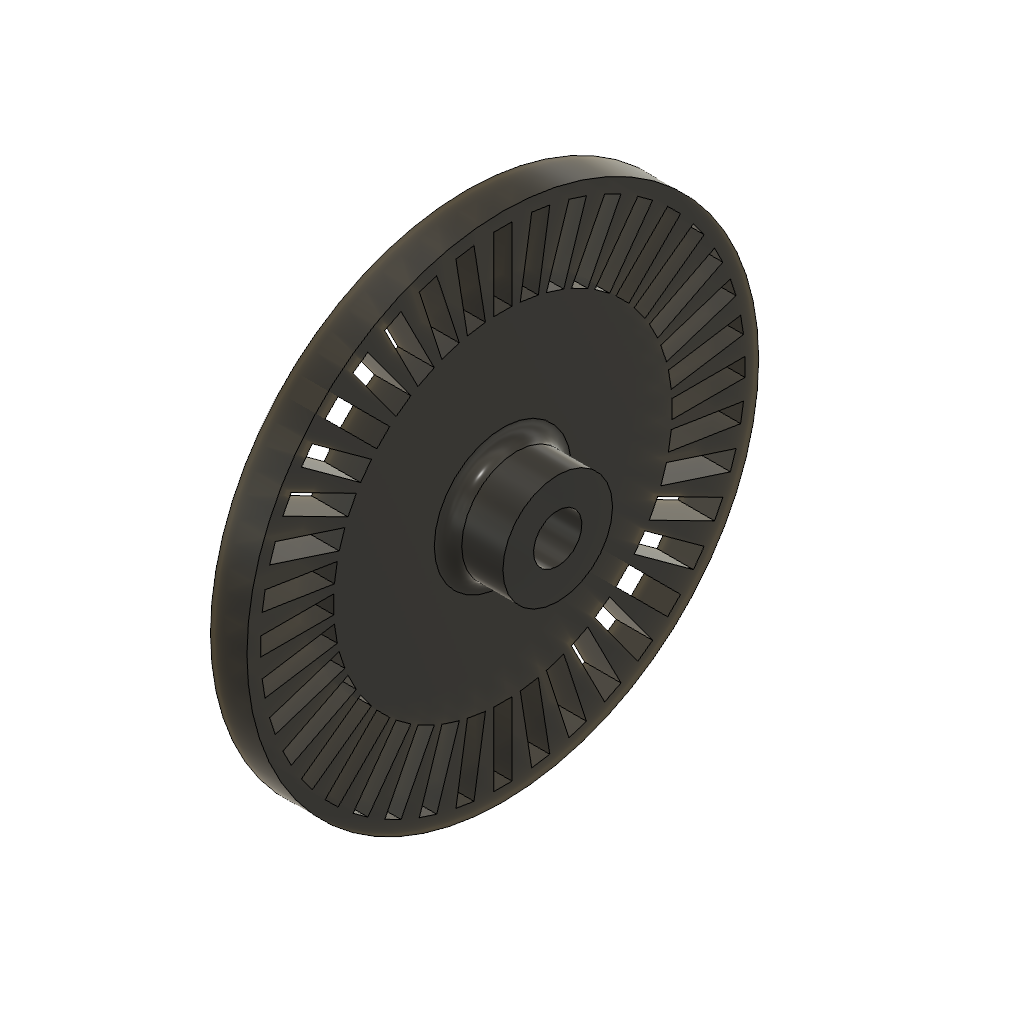
rueda_dentada_encoder (Autodesk Fusion 360 design; units mm, degrees)
Autodesk Fusion 360 part; units mm, degrees
sketch "Boceto1" plane through (0, 0, 0) normal (1, 0, 0) x (0, 0, -1)
  circle A0 centre (0, 0) radius 28
  line L0 (1.644, -2.0784) -> (1.644, 2.0784)
  line L1 (1.644, 2.0784) -> (-1.5819, -2) construction
  line L2 (-1.5819, 2) -> (1.644, -2.0784) construction
  arc A1 (1.644, 2.0784) -> (1.644, -2.0784) centre (0, 0) ccw
  circle A2 centre (0, 0) radius 26.5 construction
  line L3 (0, 0) -> (0, 29.9293) construction
  line L4 (0, 26.5) -> (-4.3464, 26.5) construction
  line L5 (0, 26.5) -> (0, 18.5)
  line L6 (0, 18.5) -> (-1, 18.5)
  line L7 (-1, 18.5) -> (-1, 26.5)
  line L8 (-1, 26.5) -> (0, 26.5)
  line L9 (1, 26.5) -> (0, 26.5)
  line L10 (1, 18.5) -> (1, 26.5)
  line L11 (0, 18.5) -> (1, 18.5)
  line L12 (-3.8817, 18.1158) -> (-5.1332, 26.0173)
  line L13 (-5.1332, 26.0173) -> (-4.1455, 26.1737)
  line L14 (-3.1578, 26.3302) -> (-4.1455, 26.1737)
  line L15 (-1.9063, 18.4287) -> (-3.1578, 26.3302)
  line L16 (-2.894, 18.2722) -> (-1.9063, 18.4287)
  line L17 (-2.894, 18.2722) -> (-3.8817, 18.1158)
  line L18 (-6.6679, 17.2855) -> (-9.14, 24.894)
  line L19 (-9.14, 24.894) -> (-8.189, 25.203)
  line L20 (-7.2379, 25.512) -> (-8.189, 25.203)
  line L21 (-4.7658, 17.9036) -> (-7.2379, 25.512)
  line L22 (-5.7168, 17.5945) -> (-4.7658, 17.9036)
  line L23 (-5.7168, 17.5945) -> (-6.6679, 17.2855)
  line L24 (-9.2898, 16.0296) -> (-12.9218, 23.1577)
  line L25 (-12.9218, 23.1577) -> (-12.0307, 23.6117)
  line L26 (-11.1397, 24.0657) -> (-12.0307, 23.6117)
  line L27 (-7.5078, 16.9376) -> (-11.1397, 24.0657)
  line L28 (-8.3988, 16.4836) -> (-7.5078, 16.9376)
  line L29 (-8.3988, 16.4836) -> (-9.2898, 16.0296)
  line L30 (-11.683, 14.379) -> (-16.3853, 20.8512)
  line L31 (-16.3853, 20.8512) -> (-15.5763, 21.439)
  line L32 (-14.7673, 22.0267) -> (-15.5763, 21.439)
  line L33 (-10.065, 15.5546) -> (-14.7673, 22.0267)
  line L34 (-10.874, 14.9668) -> (-10.065, 15.5546)
  line L35 (-10.874, 14.9668) -> (-11.683, 14.379)
  line L36 (-13.7886, 12.3744) -> (-19.4454, 18.0312)
  line L37 (-19.4454, 18.0312) -> (-18.7383, 18.7383)
  line L38 (-18.0312, 19.4454) -> (-18.7383, 18.7383)
  line L39 (-12.3744, 13.7886) -> (-18.0312, 19.4454)
  line L40 (-13.0815, 13.0815) -> (-12.3744, 13.7886)
  line L41 (-13.0815, 13.0815) -> (-13.7886, 12.3744)
  line L42 (-15.5546, 10.065) -> (-22.0267, 14.7673)
  line L43 (-22.0267, 14.7673) -> (-21.439, 15.5763)
  line L44 (-20.8512, 16.3853) -> (-21.439, 15.5763)
  line L45 (-14.379, 11.683) -> (-20.8512, 16.3853)
  line L46 (-14.9668, 10.874) -> (-14.379, 11.683)
  line L47 (-14.9668, 10.874) -> (-15.5546, 10.065)
  line L48 (-16.9376, 7.5078) -> (-24.0657, 11.1397)
  line L49 (-24.0657, 11.1397) -> (-23.6117, 12.0307)
  line L50 (-23.1577, 12.9218) -> (-23.6117, 12.0307)
  line L51 (-16.0296, 9.2898) -> (-23.1577, 12.9218)
  line L52 (-16.4836, 8.3988) -> (-16.0296, 9.2898)
  line L53 (-16.4836, 8.3988) -> (-16.9376, 7.5078)
  line L54 (-17.9036, 4.7658) -> (-25.512, 7.2379)
  line L55 (-25.512, 7.2379) -> (-25.203, 8.189)
  line L56 (-24.894, 9.14) -> (-25.203, 8.189)
  line L57 (-17.2855, 6.6679) -> (-24.894, 9.14)
  line L58 (-17.5945, 5.7168) -> (-17.2855, 6.6679)
  line L59 (-17.5945, 5.7168) -> (-17.9036, 4.7658)
  line L60 (-18.4287, 1.9063) -> (-26.3302, 3.1578)
  line L61 (-26.3302, 3.1578) -> (-26.1737, 4.1455)
  line L62 (-26.0173, 5.1332) -> (-26.1737, 4.1455)
  line L63 (-18.1158, 3.8817) -> (-26.0173, 5.1332)
  line L64 (-18.2722, 2.894) -> (-18.1158, 3.8817)
  line L65 (-18.2722, 2.894) -> (-18.4287, 1.9063)
  line L66 (-18.5, -1) -> (-26.5, -1)
  line L67 (-26.5, -1) -> (-26.5, 0)
  line L68 (-26.5, 1) -> (-26.5, 0)
  line L69 (-18.5, 1) -> (-26.5, 1)
  line L70 (-18.5, 0) -> (-18.5, 1)
  line L71 (-18.5, 0) -> (-18.5, -1)
  line L72 (-18.1158, -3.8817) -> (-26.0173, -5.1332)
  line L73 (-26.0173, -5.1332) -> (-26.1737, -4.1455)
  line L74 (-26.3302, -3.1578) -> (-26.1737, -4.1455)
  line L75 (-18.4287, -1.9063) -> (-26.3302, -3.1578)
  line L76 (-18.2722, -2.894) -> (-18.4287, -1.9063)
  line L77 (-18.2722, -2.894) -> (-18.1158, -3.8817)
  line L78 (-17.2855, -6.6679) -> (-24.894, -9.14)
  line L79 (-24.894, -9.14) -> (-25.203, -8.189)
  line L80 (-25.512, -7.2379) -> (-25.203, -8.189)
  line L81 (-17.9036, -4.7658) -> (-25.512, -7.2379)
  line L82 (-17.5945, -5.7168) -> (-17.9036, -4.7658)
  line L83 (-17.5945, -5.7168) -> (-17.2855, -6.6679)
  line L84 (-16.0296, -9.2898) -> (-23.1577, -12.9218)
  line L85 (-23.1577, -12.9218) -> (-23.6117, -12.0307)
  line L86 (-24.0657, -11.1397) -> (-23.6117, -12.0307)
  line L87 (-16.9376, -7.5078) -> (-24.0657, -11.1397)
  line L88 (-16.4836, -8.3988) -> (-16.9376, -7.5078)
  line L89 (-16.4836, -8.3988) -> (-16.0296, -9.2898)
  line L90 (-14.379, -11.683) -> (-20.8512, -16.3853)
  line L91 (-20.8512, -16.3853) -> (-21.439, -15.5763)
  line L92 (-22.0267, -14.7673) -> (-21.439, -15.5763)
  line L93 (-15.5546, -10.065) -> (-22.0267, -14.7673)
  line L94 (-14.9668, -10.874) -> (-15.5546, -10.065)
  line L95 (-14.9668, -10.874) -> (-14.379, -11.683)
  line L96 (-12.3744, -13.7886) -> (-18.0312, -19.4454)
  line L97 (-18.0312, -19.4454) -> (-18.7383, -18.7383)
  line L98 (-19.4454, -18.0312) -> (-18.7383, -18.7383)
  line L99 (-13.7886, -12.3744) -> (-19.4454, -18.0312)
  line L100 (-13.0815, -13.0815) -> (-13.7886, -12.3744)
  line L101 (-13.0815, -13.0815) -> (-12.3744, -13.7886)
  line L102 (-10.065, -15.5546) -> (-14.7673, -22.0267)
  line L103 (-14.7673, -22.0267) -> (-15.5763, -21.439)
  line L104 (-16.3853, -20.8512) -> (-15.5763, -21.439)
  line L105 (-11.683, -14.379) -> (-16.3853, -20.8512)
  line L106 (-10.874, -14.9668) -> (-11.683, -14.379)
  line L107 (-10.874, -14.9668) -> (-10.065, -15.5546)
  line L108 (-7.5078, -16.9376) -> (-11.1397, -24.0657)
  line L109 (-11.1397, -24.0657) -> (-12.0307, -23.6117)
  line L110 (-12.9218, -23.1577) -> (-12.0307, -23.6117)
  line L111 (-9.2898, -16.0296) -> (-12.9218, -23.1577)
  line L112 (-8.3988, -16.4836) -> (-9.2898, -16.0296)
  line L113 (-8.3988, -16.4836) -> (-7.5078, -16.9376)
  line L114 (-4.7658, -17.9036) -> (-7.2379, -25.512)
  line L115 (-7.2379, -25.512) -> (-8.189, -25.203)
  line L116 (-9.14, -24.894) -> (-8.189, -25.203)
  line L117 (-6.6679, -17.2855) -> (-9.14, -24.894)
  line L118 (-5.7168, -17.5945) -> (-6.6679, -17.2855)
  line L119 (-5.7168, -17.5945) -> (-4.7658, -17.9036)
  line L120 (-1.9063, -18.4287) -> (-3.1578, -26.3302)
  line L121 (-3.1578, -26.3302) -> (-4.1455, -26.1737)
  line L122 (-5.1332, -26.0173) -> (-4.1455, -26.1737)
  line L123 (-3.8817, -18.1158) -> (-5.1332, -26.0173)
  line L124 (-2.894, -18.2722) -> (-3.8817, -18.1158)
  line L125 (-2.894, -18.2722) -> (-1.9063, -18.4287)
  line L126 (1, -18.5) -> (1, -26.5)
  line L127 (1, -26.5) -> (0, -26.5)
  line L128 (-1, -26.5) -> (0, -26.5)
  line L129 (-1, -18.5) -> (-1, -26.5)
  line L130 (0, -18.5) -> (-1, -18.5)
  line L131 (0, -18.5) -> (1, -18.5)
  line L132 (3.8817, -18.1158) -> (5.1332, -26.0173)
  line L133 (5.1332, -26.0173) -> (4.1455, -26.1737)
  line L134 (3.1578, -26.3302) -> (4.1455, -26.1737)
  line L135 (1.9063, -18.4287) -> (3.1578, -26.3302)
  line L136 (2.894, -18.2722) -> (1.9063, -18.4287)
  line L137 (2.894, -18.2722) -> (3.8817, -18.1158)
  line L138 (6.6679, -17.2855) -> (9.14, -24.894)
  line L139 (9.14, -24.894) -> (8.189, -25.203)
  line L140 (7.2379, -25.512) -> (8.189, -25.203)
  line L141 (4.7658, -17.9036) -> (7.2379, -25.512)
  line L142 (5.7168, -17.5945) -> (4.7658, -17.9036)
  line L143 (5.7168, -17.5945) -> (6.6679, -17.2855)
  line L144 (9.2898, -16.0296) -> (12.9218, -23.1577)
  line L145 (12.9218, -23.1577) -> (12.0307, -23.6117)
  line L146 (11.1397, -24.0657) -> (12.0307, -23.6117)
  line L147 (7.5078, -16.9376) -> (11.1397, -24.0657)
  line L148 (8.3988, -16.4836) -> (7.5078, -16.9376)
  line L149 (8.3988, -16.4836) -> (9.2898, -16.0296)
  line L150 (11.683, -14.379) -> (16.3853, -20.8512)
  line L151 (16.3853, -20.8512) -> (15.5763, -21.439)
  line L152 (14.7673, -22.0267) -> (15.5763, -21.439)
  line L153 (10.065, -15.5546) -> (14.7673, -22.0267)
  line L154 (10.874, -14.9668) -> (10.065, -15.5546)
  line L155 (10.874, -14.9668) -> (11.683, -14.379)
  line L156 (13.7886, -12.3744) -> (19.4454, -18.0312)
  line L157 (19.4454, -18.0312) -> (18.7383, -18.7383)
  line L158 (18.0312, -19.4454) -> (18.7383, -18.7383)
  line L159 (12.3744, -13.7886) -> (18.0312, -19.4454)
  line L160 (13.0815, -13.0815) -> (12.3744, -13.7886)
  line L161 (13.0815, -13.0815) -> (13.7886, -12.3744)
  line L162 (15.5546, -10.065) -> (22.0267, -14.7673)
  line L163 (22.0267, -14.7673) -> (21.439, -15.5763)
  line L164 (20.8512, -16.3853) -> (21.439, -15.5763)
  line L165 (14.379, -11.683) -> (20.8512, -16.3853)
  line L166 (14.9668, -10.874) -> (14.379, -11.683)
  line L167 (14.9668, -10.874) -> (15.5546, -10.065)
  line L168 (16.9376, -7.5078) -> (24.0657, -11.1397)
  line L169 (24.0657, -11.1397) -> (23.6117, -12.0307)
  line L170 (23.1577, -12.9218) -> (23.6117, -12.0307)
  line L171 (16.0296, -9.2898) -> (23.1577, -12.9218)
  line L172 (16.4836, -8.3988) -> (16.0296, -9.2898)
  line L173 (16.4836, -8.3988) -> (16.9376, -7.5078)
  line L174 (17.9036, -4.7658) -> (25.512, -7.2379)
  line L175 (25.512, -7.2379) -> (25.203, -8.189)
  line L176 (24.894, -9.14) -> (25.203, -8.189)
  line L177 (17.2855, -6.6679) -> (24.894, -9.14)
  line L178 (17.5945, -5.7168) -> (17.2855, -6.6679)
  line L179 (17.5945, -5.7168) -> (17.9036, -4.7658)
  line L180 (18.4287, -1.9063) -> (26.3302, -3.1578)
  line L181 (26.3302, -3.1578) -> (26.1737, -4.1455)
  line L182 (26.0173, -5.1332) -> (26.1737, -4.1455)
  line L183 (18.1158, -3.8817) -> (26.0173, -5.1332)
  line L184 (18.2722, -2.894) -> (18.1158, -3.8817)
  line L185 (18.2722, -2.894) -> (18.4287, -1.9063)
  line L186 (18.5, 1) -> (26.5, 1)
  line L187 (26.5, 1) -> (26.5, 0)
  line L188 (26.5, -1) -> (26.5, 0)
  line L189 (18.5, -1) -> (26.5, -1)
  line L190 (18.5, 0) -> (18.5, -1)
  line L191 (18.5, 0) -> (18.5, 1)
  line L192 (18.1158, 3.8817) -> (26.0173, 5.1332)
  line L193 (26.0173, 5.1332) -> (26.1737, 4.1455)
  line L194 (26.3302, 3.1578) -> (26.1737, 4.1455)
  line L195 (18.4287, 1.9063) -> (26.3302, 3.1578)
  line L196 (18.2722, 2.894) -> (18.4287, 1.9063)
  line L197 (18.2722, 2.894) -> (18.1158, 3.8817)
  line L198 (17.2855, 6.6679) -> (24.894, 9.14)
  line L199 (24.894, 9.14) -> (25.203, 8.189)
  line L200 (25.512, 7.2379) -> (25.203, 8.189)
  line L201 (17.9036, 4.7658) -> (25.512, 7.2379)
  line L202 (17.5945, 5.7168) -> (17.9036, 4.7658)
  line L203 (17.5945, 5.7168) -> (17.2855, 6.6679)
  line L204 (16.0296, 9.2898) -> (23.1577, 12.9218)
  line L205 (23.1577, 12.9218) -> (23.6117, 12.0307)
  line L206 (24.0657, 11.1397) -> (23.6117, 12.0307)
  line L207 (16.9376, 7.5078) -> (24.0657, 11.1397)
  line L208 (16.4836, 8.3988) -> (16.9376, 7.5078)
  line L209 (16.4836, 8.3988) -> (16.0296, 9.2898)
  line L210 (14.379, 11.683) -> (20.8512, 16.3853)
  line L211 (20.8512, 16.3853) -> (21.439, 15.5763)
  line L212 (22.0267, 14.7673) -> (21.439, 15.5763)
  line L213 (15.5546, 10.065) -> (22.0267, 14.7673)
  line L214 (14.9668, 10.874) -> (15.5546, 10.065)
  line L215 (14.9668, 10.874) -> (14.379, 11.683)
  line L216 (12.3744, 13.7886) -> (18.0312, 19.4454)
  line L217 (18.0312, 19.4454) -> (18.7383, 18.7383)
  line L218 (19.4454, 18.0312) -> (18.7383, 18.7383)
  line L219 (13.7886, 12.3744) -> (19.4454, 18.0312)
  line L220 (13.0815, 13.0815) -> (13.7886, 12.3744)
  line L221 (13.0815, 13.0815) -> (12.3744, 13.7886)
  line L222 (10.065, 15.5546) -> (14.7673, 22.0267)
  line L223 (14.7673, 22.0267) -> (15.5763, 21.439)
  line L224 (16.3853, 20.8512) -> (15.5763, 21.439)
  line L225 (11.683, 14.379) -> (16.3853, 20.8512)
  line L226 (10.874, 14.9668) -> (11.683, 14.379)
  line L227 (10.874, 14.9668) -> (10.065, 15.5546)
  line L228 (7.5078, 16.9376) -> (11.1397, 24.0657)
  line L229 (11.1397, 24.0657) -> (12.0307, 23.6117)
  line L230 (12.9218, 23.1577) -> (12.0307, 23.6117)
  line L231 (9.2898, 16.0296) -> (12.9218, 23.1577)
  line L232 (8.3988, 16.4836) -> (9.2898, 16.0296)
  line L233 (8.3988, 16.4836) -> (7.5078, 16.9376)
  line L234 (4.7658, 17.9036) -> (7.2379, 25.512)
  line L235 (7.2379, 25.512) -> (8.189, 25.203)
  line L236 (9.14, 24.894) -> (8.189, 25.203)
  line L237 (6.6679, 17.2855) -> (9.14, 24.894)
  line L238 (5.7168, 17.5945) -> (6.6679, 17.2855)
  line L239 (5.7168, 17.5945) -> (4.7658, 17.9036)
  line L240 (1.9063, 18.4287) -> (3.1578, 26.3302)
  line L241 (3.1578, 26.3302) -> (4.1455, 26.1737)
  line L242 (5.1332, 26.0173) -> (4.1455, 26.1737)
  line L243 (3.8817, 18.1158) -> (5.1332, 26.0173)
  line L244 (2.894, 18.2722) -> (3.8817, 18.1158)
  line L245 (2.894, 18.2722) -> (1.9063, 18.4287)
  dimension "d1" = 56
  dimension "d2" = 5.3
  dimension "d3" = 4
  dimension "d4" = 53
  dimension "d5" = 8
  dimension "d6" = 1
  dimension "d8" = 360
  constraint coincident A0.centre A1.centre
  constraint coincident L1 A0.centre
  constraint coincident L2 A0.centre
  constraint concentric A1 A2
  constraint vertical L3
  constraint coincident A2 L4.start
  constraint coincident L3 L4.start
  constraint tangent A2 L4
  constraint perpendicular L5 L6
  constraint parallel L5 L7
  constraint parallel L6 L8
  constraint coincident L3 L5.end
  constraint symmetric L3 L4.start L5.start
  constraint symmetric L3 L5.end L6.start
  constraint symmetric L3 L6.end L10.start
  constraint symmetric L3 L7.end L9.start
  measures "d1" diameter of A0
  measures "d2" diameter of A1
  measures "d3" distance of L2.start L1.end
  measures "d4" diameter of A2
  measures "d5" distance of L4.start L5.end
  measures "d6" distance of L4.start L7.end
extrude "Extruir1" add sketch "Boceto1" along normal blind 4
sketch "Boceto2" plane through (4, 0, 0) normal (1, 0, 0) x (0, 0, -1)
  line L0 (5.1332, 26.0173) -> (3.8817, 18.1158)
  line L1 (3.8817, 18.1158) -> (1.9063, 18.4287)
  line L2 (1.9063, 18.4287) -> (3.1578, 26.3302)
  line L3 (3.1578, 26.3302) -> (5.1332, 26.0173)
  line L4 (19.4454, 18.0312) -> (13.7886, 12.3744)
  line L5 (13.7886, 12.3744) -> (12.3744, 13.7886)
  line L6 (12.3744, 13.7886) -> (18.0312, 19.4454)
  line L7 (18.0312, 19.4454) -> (19.4454, 18.0312)
  line L8 (12.9218, 23.1577) -> (9.2898, 16.0296)
  line L9 (9.2898, 16.0296) -> (7.5078, 16.9376)
  line L10 (7.5078, 16.9376) -> (11.1397, 24.0657)
  line L11 (11.1397, 24.0657) -> (12.9218, 23.1577)
  line L12 (-25.512, -7.2379) -> (-17.9036, -4.7658)
  line L13 (-17.9036, -4.7658) -> (-17.2855, -6.6679)
  line L14 (-17.2855, -6.6679) -> (-24.894, -9.14)
  line L15 (-24.894, -9.14) -> (-25.512, -7.2379)
  line L16 (-26.5, 1) -> (-18.5, 1)
  line L17 (-18.5, 1) -> (-18.5, -1)
  line L18 (-18.5, -1) -> (-26.5, -1)
  line L19 (-26.5, -1) -> (-26.5, 1)
  line L20 (-26.0173, 5.1332) -> (-18.1158, 3.8817)
  line L21 (-18.1158, 3.8817) -> (-18.4287, 1.9063)
  line L22 (-18.4287, 1.9063) -> (-26.3302, 3.1578)
  line L23 (-26.3302, 3.1578) -> (-26.0173, 5.1332)
  line L24 (16.3853, 20.8512) -> (11.683, 14.379)
  line L25 (11.683, 14.379) -> (10.065, 15.5546)
  line L26 (10.065, 15.5546) -> (14.7673, 22.0267)
  line L27 (14.7673, 22.0267) -> (16.3853, 20.8512)
  line L28 (-24.894, 9.14) -> (-17.2855, 6.6679)
  line L29 (-17.2855, 6.6679) -> (-17.9036, 4.7658)
  line L30 (-17.9036, 4.7658) -> (-25.512, 7.2379)
  line L31 (-25.512, 7.2379) -> (-24.894, 9.14)
  line L32 (-20.8512, 16.3853) -> (-14.379, 11.683)
  line L33 (-14.379, 11.683) -> (-15.5546, 10.065)
  line L34 (-15.5546, 10.065) -> (-22.0267, 14.7673)
  line L35 (-22.0267, 14.7673) -> (-20.8512, 16.3853)
  line L36 (-18.0312, 19.4454) -> (-12.3744, 13.7886)
  line L37 (-12.3744, 13.7886) -> (-13.7886, 12.3744)
  line L38 (-13.7886, 12.3744) -> (-19.4454, 18.0312)
  line L39 (-19.4454, 18.0312) -> (-18.0312, 19.4454)
  arc A0 (1.644, 2.0784) -> (1.644, -2.0784) centre (0, 0) ccw
  line L40 (1.644, 2.0784) -> (1.644, -2.0784)
  line L41 (-3.1578, 26.3302) -> (-1.9063, 18.4287)
  line L42 (-1.9063, 18.4287) -> (-3.8817, 18.1158)
  line L43 (-3.8817, 18.1158) -> (-5.1332, 26.0173)
  line L44 (-5.1332, 26.0173) -> (-3.1578, 26.3302)
  line L45 (-7.2379, 25.512) -> (-4.7658, 17.9036)
  line L46 (-4.7658, 17.9036) -> (-6.6679, 17.2855)
  line L47 (-6.6679, 17.2855) -> (-9.14, 24.894)
  line L48 (-9.14, 24.894) -> (-7.2379, 25.512)
  line L49 (-11.1397, 24.0657) -> (-7.5078, 16.9376)
  line L50 (-7.5078, 16.9376) -> (-9.2898, 16.0296)
  line L51 (-9.2898, 16.0296) -> (-12.9218, 23.1577)
  line L52 (-12.9218, 23.1577) -> (-11.1397, 24.0657)
  line L53 (-14.7673, 22.0267) -> (-10.065, 15.5546)
  line L54 (-10.065, 15.5546) -> (-11.683, 14.379)
  line L55 (-11.683, 14.379) -> (-16.3853, 20.8512)
  line L56 (-16.3853, 20.8512) -> (-14.7673, 22.0267)
  line L57 (-12.9218, -23.1577) -> (-9.2898, -16.0296)
  line L58 (-9.2898, -16.0296) -> (-7.5078, -16.9376)
  line L59 (-7.5078, -16.9376) -> (-11.1397, -24.0657)
  line L60 (-11.1397, -24.0657) -> (-12.9218, -23.1577)
  line L61 (-5.1332, -26.0173) -> (-3.8817, -18.1158)
  line L62 (-3.8817, -18.1158) -> (-1.9063, -18.4287)
  line L63 (-1.9063, -18.4287) -> (-3.1578, -26.3302)
  line L64 (-3.1578, -26.3302) -> (-5.1332, -26.0173)
  line L65 (-19.4454, -18.0312) -> (-13.7886, -12.3744)
  line L66 (-13.7886, -12.3744) -> (-12.3744, -13.7886)
  line L67 (-12.3744, -13.7886) -> (-18.0312, -19.4454)
  line L68 (-18.0312, -19.4454) -> (-19.4454, -18.0312)
  line L69 (9.14, 24.894) -> (6.6679, 17.2855)
  line L70 (6.6679, 17.2855) -> (4.7658, 17.9036)
  line L71 (4.7658, 17.9036) -> (7.2379, 25.512)
  line L72 (7.2379, 25.512) -> (9.14, 24.894)
  line L73 (-9.14, -24.894) -> (-6.6679, -17.2855)
  line L74 (-6.6679, -17.2855) -> (-4.7658, -17.9036)
  line L75 (-4.7658, -17.9036) -> (-7.2379, -25.512)
  line L76 (-7.2379, -25.512) -> (-9.14, -24.894)
  line L77 (20.8512, -16.3853) -> (14.379, -11.683)
  line L78 (14.379, -11.683) -> (15.5546, -10.065)
  line L79 (15.5546, -10.065) -> (22.0267, -14.7673)
  line L80 (22.0267, -14.7673) -> (20.8512, -16.3853)
  line L81 (-24.0657, -11.1397) -> (-16.9376, -7.5078)
  line L82 (-16.9376, -7.5078) -> (-16.0296, -9.2898)
  line L83 (-16.0296, -9.2898) -> (-23.1577, -12.9218)
  line L84 (-23.1577, -12.9218) -> (-24.0657, -11.1397)
  line L85 (23.1577, -12.9218) -> (16.0296, -9.2898)
  line L86 (16.0296, -9.2898) -> (16.9376, -7.5078)
  line L87 (16.9376, -7.5078) -> (24.0657, -11.1397)
  line L88 (24.0657, -11.1397) -> (23.1577, -12.9218)
  line L89 (-1, -26.5) -> (-1, -18.5)
  line L90 (-1, -18.5) -> (1, -18.5)
  line L91 (1, -18.5) -> (1, -26.5)
  line L92 (1, -26.5) -> (-1, -26.5)
  line L93 (14.7673, -22.0267) -> (10.065, -15.5546)
  line L94 (10.065, -15.5546) -> (11.683, -14.379)
  line L95 (11.683, -14.379) -> (16.3853, -20.8512)
  line L96 (16.3853, -20.8512) -> (14.7673, -22.0267)
  line L97 (24.894, -9.14) -> (17.2855, -6.6679)
  line L98 (17.2855, -6.6679) -> (17.9036, -4.7658)
  line L99 (17.9036, -4.7658) -> (25.512, -7.2379)
  line L100 (25.512, -7.2379) -> (24.894, -9.14)
  line L101 (26.0173, -5.1332) -> (18.1158, -3.8817)
  line L102 (18.1158, -3.8817) -> (18.4287, -1.9063)
  line L103 (18.4287, -1.9063) -> (26.3302, -3.1578)
  line L104 (26.3302, -3.1578) -> (26.0173, -5.1332)
  line L105 (-26.3302, -3.1578) -> (-18.4287, -1.9063)
  line L106 (-18.4287, -1.9063) -> (-18.1158, -3.8817)
  line L107 (-18.1158, -3.8817) -> (-26.0173, -5.1332)
  line L108 (-26.0173, -5.1332) -> (-26.3302, -3.1578)
  line L109 (3.1578, -26.3302) -> (1.9063, -18.4287)
  line L110 (1.9063, -18.4287) -> (3.8817, -18.1158)
  line L111 (3.8817, -18.1158) -> (5.1332, -26.0173)
  line L112 (5.1332, -26.0173) -> (3.1578, -26.3302)
  line L113 (-22.0267, -14.7673) -> (-15.5546, -10.065)
  line L114 (-15.5546, -10.065) -> (-14.379, -11.683)
  line L115 (-14.379, -11.683) -> (-20.8512, -16.3853)
  line L116 (-20.8512, -16.3853) -> (-22.0267, -14.7673)
  line L117 (26.5, -1) -> (18.5, -1)
  line L118 (18.5, -1) -> (18.5, 1)
  line L119 (18.5, 1) -> (26.5, 1)
  line L120 (26.5, 1) -> (26.5, -1)
  line L121 (7.2379, -25.512) -> (4.7658, -17.9036)
  line L122 (4.7658, -17.9036) -> (6.6679, -17.2855)
  line L123 (6.6679, -17.2855) -> (9.14, -24.894)
  line L124 (9.14, -24.894) -> (7.2379, -25.512)
  line L125 (11.1397, -24.0657) -> (7.5078, -16.9376)
  line L126 (7.5078, -16.9376) -> (9.2898, -16.0296)
  line L127 (9.2898, -16.0296) -> (12.9218, -23.1577)
  line L128 (12.9218, -23.1577) -> (11.1397, -24.0657)
  line L129 (25.512, 7.2379) -> (17.9036, 4.7658)
  line L130 (17.9036, 4.7658) -> (17.2855, 6.6679)
  line L131 (17.2855, 6.6679) -> (24.894, 9.14)
  line L132 (24.894, 9.14) -> (25.512, 7.2379)
  line L133 (1, 18.5) -> (-1, 18.5)
  line L134 (-1, 18.5) -> (-1, 26.5)
  line L135 (-1, 26.5) -> (1, 26.5)
  line L136 (1, 26.5) -> (1, 18.5)
  line L137 (22.0267, 14.7673) -> (15.5546, 10.065)
  line L138 (15.5546, 10.065) -> (14.379, 11.683)
  line L139 (14.379, 11.683) -> (20.8512, 16.3853)
  line L140 (20.8512, 16.3853) -> (22.0267, 14.7673)
  line L141 (18.0312, -19.4454) -> (12.3744, -13.7886)
  line L142 (12.3744, -13.7886) -> (13.7886, -12.3744)
  line L143 (13.7886, -12.3744) -> (19.4454, -18.0312)
  line L144 (19.4454, -18.0312) -> (18.0312, -19.4454)
  line L145 (26.3302, 3.1578) -> (18.4287, 1.9063)
  line L146 (18.4287, 1.9063) -> (18.1158, 3.8817)
  line L147 (18.1158, 3.8817) -> (26.0173, 5.1332)
  line L148 (26.0173, 5.1332) -> (26.3302, 3.1578)
  line L149 (24.0657, 11.1397) -> (16.9376, 7.5078)
  line L150 (16.9376, 7.5078) -> (16.0296, 9.2898)
  line L151 (16.0296, 9.2898) -> (23.1577, 12.9218)
  line L152 (23.1577, 12.9218) -> (24.0657, 11.1397)
  line L153 (-16.3853, -20.8512) -> (-11.683, -14.379)
  line L154 (-11.683, -14.379) -> (-10.065, -15.5546)
  line L155 (-10.065, -15.5546) -> (-14.7673, -22.0267)
  line L156 (-14.7673, -22.0267) -> (-16.3853, -20.8512)
  line L157 (-23.1577, 12.9218) -> (-16.0296, 9.2898)
  line L158 (-16.0296, 9.2898) -> (-16.9376, 7.5078)
  line L159 (-16.9376, 7.5078) -> (-24.0657, 11.1397)
  line L160 (-24.0657, 11.1397) -> (-23.1577, 12.9218)
  circle A1 centre (0, 0) radius 28
  circle A2 centre (0, 0) radius 2.65
  circle A3 centre (0, 0) radius 6
  dimension "d11" = 12
  dimension "d14" = 5.3
  constraint concentric A0 A2
  constraint coincident A0.centre A1.centre
  measures "d11" diameter of A3
  measures "d14" diameter of A2
extrude "Extruir2" add sketch "Boceto2" along normal blind 6 contours A3
fillet "Empalme1" radius 1.5 1 edges at (4, 2.1697, 5.594)
